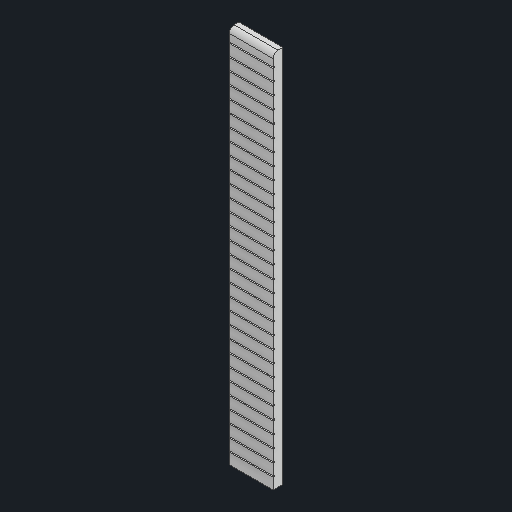
# Autodesk Inventor part: 7_1_4_vollet_cote_arriere
Saved by Autodesk Inventor 2026 (Build 300175000, 175)
## iProperties
Created: 2025-06-21
Part Number: 7_1_4_vollet_cote_arriere
Material: Generic
Document SubType Name: Modeling
Designer: remg9
Density: 1 g/cm^3
Appearance: Default
Author: remg9
Autodesk Inventor part; units mm, degrees
ref_plane "YZ Plane" through (0, 0, 0) normal (1, 0, 0) x (0, 1, 0)
ref_plane "XZ Plane" through (0, 0, 0) normal (0, 1, 0) x (-1, 0, 0)
ref_plane "XY Plane" through (0, 0, 0) normal (0, 0, 1) x (1, 0, 0)
sketch "Sketch1" plane through (0, 0, 0) normal (0, 0, 1) x (1, 0, 0)
  line L0 (0, 0) -> (18, 0)
  line L1 (18, 0) -> (18, 155)
  line L2 (18, 155) -> (0, 155)
  line L3 (0, 155) -> (0, 0)
  dimension "d0" = 18
  dimension "d1" = 155
  constraints: 8 end point, 2 parallel, 1 horizontal, 1 perpendicular
  measures "d0" distance of L1.end L2.end
  measures "d1" distance of L0.end L1.end
extrude "Extrusion1" add sketch "Sketch1" along normal blind 4
sketch "Sketch2" plane through (0, 0, 4) normal (0, 0, 1) x (1, 0, 0)
  line L0 (0, 150) -> (18, 150)
  line L1 (18, 150) -> (18, 149.5)
  line L2 (18, 149.5) -> (0, 149.5)
  line L3 (0, 149.5) -> (0, 150)
  line L4 (0, 155) -> (0, 0) projected
  line L5 (18, 0) -> (18, 155) projected
  line L6 (18, 155) -> (0, 155) projected
  line L7 (0, 145) -> (18, 145)
  line L8 (18, 145) -> (18, 144.5)
  line L9 (18, 144.5) -> (0, 144.5)
  line L10 (0, 144.5) -> (0, 145)
  line L11 (0, 140) -> (18, 140)
  line L12 (18, 140) -> (18, 139.5)
  line L13 (18, 139.5) -> (0, 139.5)
  line L14 (0, 139.5) -> (0, 140)
  line L15 (0, 135) -> (18, 135)
  line L16 (18, 135) -> (18, 134.5)
  line L17 (18, 134.5) -> (0, 134.5)
  line L18 (0, 134.5) -> (0, 135)
  line L19 (0, 130) -> (18, 130)
  line L20 (18, 130) -> (18, 129.5)
  line L21 (18, 129.5) -> (0, 129.5)
  line L22 (0, 129.5) -> (0, 130)
  line L23 (0, 125) -> (18, 125)
  line L24 (18, 125) -> (18, 124.5)
  line L25 (18, 124.5) -> (0, 124.5)
  line L26 (0, 124.5) -> (0, 125)
  line L27 (0, 120) -> (18, 120)
  line L28 (18, 120) -> (18, 119.5)
  line L29 (18, 119.5) -> (0, 119.5)
  line L30 (0, 119.5) -> (0, 120)
  line L31 (0, 115) -> (18, 115)
  line L32 (18, 115) -> (18, 114.5)
  line L33 (18, 114.5) -> (0, 114.5)
  line L34 (0, 114.5) -> (0, 115)
  line L35 (0, 110) -> (18, 110)
  line L36 (18, 110) -> (18, 109.5)
  line L37 (18, 109.5) -> (0, 109.5)
  line L38 (0, 109.5) -> (0, 110)
  line L39 (0, 105) -> (18, 105)
  line L40 (18, 105) -> (18, 104.5)
  line L41 (18, 104.5) -> (0, 104.5)
  line L42 (0, 104.5) -> (0, 105)
  line L43 (0, 100) -> (18, 100)
  line L44 (18, 100) -> (18, 99.5)
  line L45 (18, 99.5) -> (0, 99.5)
  line L46 (0, 99.5) -> (0, 100)
  line L47 (0, 95) -> (18, 95)
  line L48 (18, 95) -> (18, 94.5)
  line L49 (18, 94.5) -> (0, 94.5)
  line L50 (0, 94.5) -> (0, 95)
  line L51 (0, 90) -> (18, 90)
  line L52 (18, 90) -> (18, 89.5)
  line L53 (18, 89.5) -> (0, 89.5)
  line L54 (0, 89.5) -> (0, 90)
  line L55 (0, 85) -> (18, 85)
  line L56 (18, 85) -> (18, 84.5)
  line L57 (18, 84.5) -> (0, 84.5)
  line L58 (0, 84.5) -> (0, 85)
  line L59 (0, 80) -> (18, 80)
  line L60 (18, 80) -> (18, 79.5)
  line L61 (18, 79.5) -> (0, 79.5)
  line L62 (0, 79.5) -> (0, 80)
  line L63 (0, 75) -> (18, 75)
  line L64 (18, 75) -> (18, 74.5)
  line L65 (18, 74.5) -> (0, 74.5)
  line L66 (0, 74.5) -> (0, 75)
  line L67 (0, 70) -> (18, 70)
  line L68 (18, 70) -> (18, 69.5)
  line L69 (18, 69.5) -> (0, 69.5)
  line L70 (0, 69.5) -> (0, 70)
  line L71 (0, 65) -> (18, 65)
  line L72 (18, 65) -> (18, 64.5)
  line L73 (18, 64.5) -> (0, 64.5)
  line L74 (0, 64.5) -> (0, 65)
  line L75 (0, 60) -> (18, 60)
  line L76 (18, 60) -> (18, 59.5)
  line L77 (18, 59.5) -> (0, 59.5)
  line L78 (0, 59.5) -> (0, 60)
  line L79 (0, 55) -> (18, 55)
  line L80 (18, 55) -> (18, 54.5)
  line L81 (18, 54.5) -> (0, 54.5)
  line L82 (0, 54.5) -> (0, 55)
  line L83 (0, 50) -> (18, 50)
  line L84 (18, 50) -> (18, 49.5)
  line L85 (18, 49.5) -> (0, 49.5)
  line L86 (0, 49.5) -> (0, 50)
  line L87 (0, 45) -> (18, 45)
  line L88 (18, 45) -> (18, 44.5)
  line L89 (18, 44.5) -> (0, 44.5)
  line L90 (0, 44.5) -> (0, 45)
  line L91 (0, 40) -> (18, 40)
  line L92 (18, 40) -> (18, 39.5)
  line L93 (18, 39.5) -> (0, 39.5)
  line L94 (0, 39.5) -> (0, 40)
  line L95 (0, 35) -> (18, 35)
  line L96 (18, 35) -> (18, 34.5)
  line L97 (18, 34.5) -> (0, 34.5)
  line L98 (0, 34.5) -> (0, 35)
  line L99 (0, 30) -> (18, 30)
  line L100 (18, 30) -> (18, 29.5)
  line L101 (18, 29.5) -> (0, 29.5)
  line L102 (0, 29.5) -> (0, 30)
  line L103 (0, 25) -> (18, 25)
  line L104 (18, 25) -> (18, 24.5)
  line L105 (18, 24.5) -> (0, 24.5)
  line L106 (0, 24.5) -> (0, 25)
  line L107 (0, 20) -> (18, 20)
  line L108 (18, 20) -> (18, 19.5)
  line L109 (18, 19.5) -> (0, 19.5)
  line L110 (0, 19.5) -> (0, 20)
  line L111 (0, 15) -> (18, 15)
  line L112 (18, 15) -> (18, 14.5)
  line L113 (18, 14.5) -> (0, 14.5)
  line L114 (0, 14.5) -> (0, 15)
  line L115 (0, 10) -> (18, 10)
  line L116 (18, 10) -> (18, 9.5)
  line L117 (18, 9.5) -> (0, 9.5)
  line L118 (0, 9.5) -> (0, 10)
  line L119 (0, 5) -> (18, 5)
  line L120 (18, 5) -> (18, 4.5)
  line L121 (18, 4.5) -> (0, 4.5)
  line L122 (0, 4.5) -> (0, 5)
  point P0 (0, 14.5)
  point P1 (0, 9.5)
  point P2 (0, 4.5)
  point P3 (0, 19.5)
  point P4 (0, 24.5)
  point P5 (0, 29.5)
  point P6 (0, 34.5)
  point P7 (0, 39.5)
  point P8 (0, 44.5)
  point P9 (0, 49.5)
  point P10 (0, 54.5)
  point P11 (0, 59.5)
  point P12 (0, 64.5)
  point P13 (0, 69.5)
  point P14 (0, 74.5)
  point P15 (0, 79.5)
  point P16 (0, 84.5)
  point P17 (0, 89.5)
  point P18 (0, 94.5)
  point P19 (0, 99.5)
  point P20 (0, 104.5)
  point P21 (0, 109.5)
  point P22 (0, 114.5)
  point P23 (0, 119.5)
  point P24 (0, 124.5)
  point P25 (0, 129.5)
  point P26 (0, 134.5)
  point P27 (0, 139.5)
  point P28 (0, 144.5)
  dimension "d4" = 0.5
  dimension "d5" = 5
  dimension "d8" = 5
  constraints: 240 end point, 116 vertical alignment, 60 parallel, 58 collinear, 2 vertical, 1 horizontal, 1 perpendicular, 2 other
  measures "d4" distance between parallel lines of L2 L0
  measures "d5" distance between parallel lines of L6 L0
  measures "d8" distance of L0.start L7.start
extrude "Extrusion2" cut sketch "Sketch2" against normal blind 0.5 contours L0 L1 L2 L3 | L7 L5 L9 L4 | L11 L5 L13 L4 | L15 L5 L17 L4 | L19 L5 L21 L4 | L23 L5 L25 L4 | L27 L5 L29 L4 | L31 L5 L33 L4 | L35 L5 L37 L4 | L39 L5 L41 L4 | L43 L5 L45 L4 | L47 L5 L49 L4 | L51 L5 L53 L4 | L55 L5 L57 L4 | L59 L5 L61 L4 | L63 L5 L65 L4 | L67 L5 L69 L4 | L71 L5 L73 L4 | L75 L5 L77 L4 | L79 L5 L81 L4 | L83 L5 L85 L4 | L87 L5 L89 L4 | L91 L5 L93 L4 | L95 L5 L97 L4 | L99 L5 L101 L4 | L103 L5 L105 L4 | L107 L5 L109 L4 | L111 L5 L113 L4 | L115 L5 L117 L4 | L119 L5 L121 L4
fillet "Fillet1" radius 2 1 edges at (9, 155, 4)
body "Solid1"
